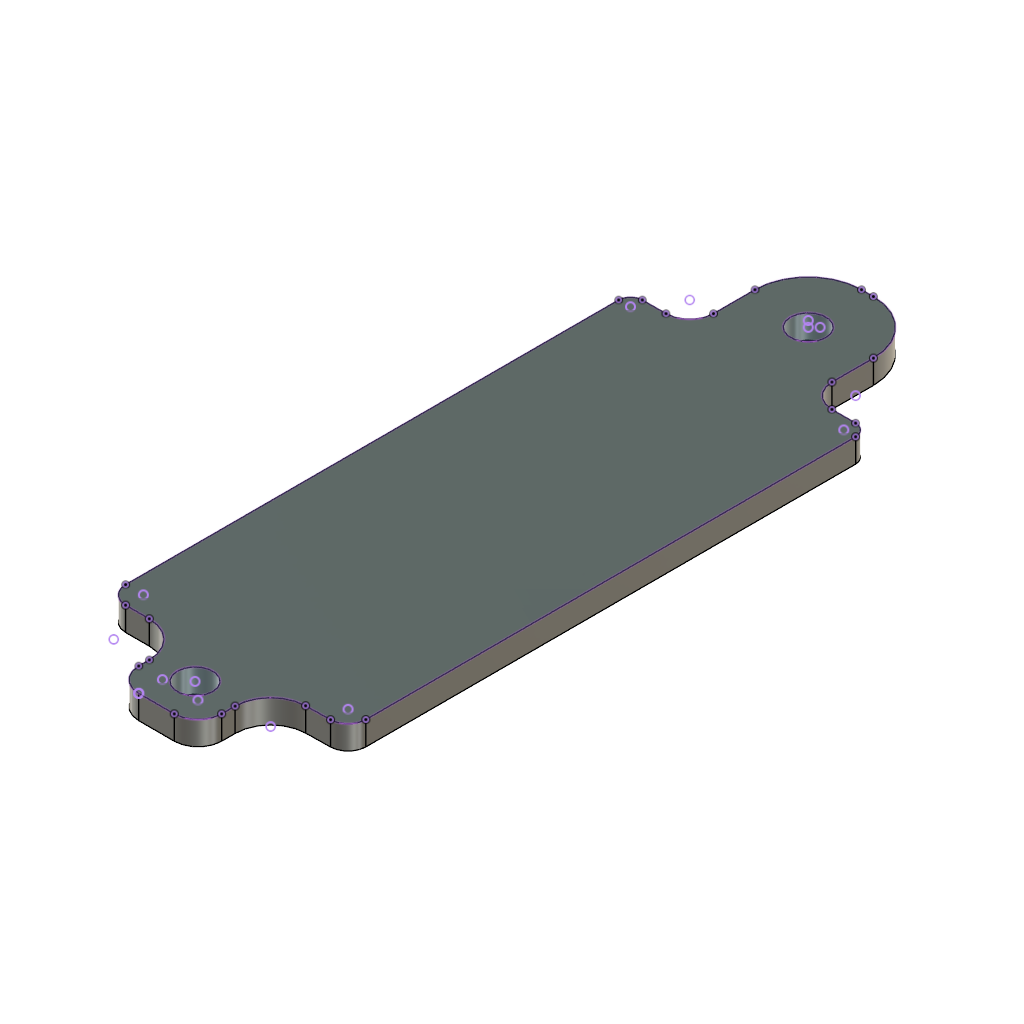
IM_glove_2 (Autodesk Fusion 360 archive; units mm, degrees)
design "fleje 20mm"
Autodesk Fusion 360 part; units mm, degrees
sketch "Boceto1" plane through (0, 0, 0) normal (0, 0, 1) x (1, 0, 0)
  line L0 (0, 0) -> (0, 45)
  line L1 (0, 45) -> (0, 55)
  line L2 (0, 55) -> (0, 50)
  circle A0 centre (0, 50) radius 1.5
  line L3 (0, 0) -> (0, -3.5)
  line L4 (0, -3.5) -> (0, -1.75)
  circle A1 centre (0, -1.75) radius 1.5
  line L5 (0, 0) -> (0, 17.5)
  line L6 (0, 17.5) -> (0, 45)
  line L7 (-7, 45) -> (-9, 45)
  line L8 (7, 45) -> (9, 45)
  line L9 (10, 44) -> (10, 2.6675)
  line L10 (-6.5, 0.8929) -> (-8.5, 0.8929)
  line L11 (-10, 2.3929) -> (-10, 44)
  line L12 (0, 0) -> (-3.5, 0)
  line L13 (0, 0) -> (3.5, 0)
  line L14 (-3.5, 0) -> (3.5, 0)
  line L15 (3.5, -1.8653) -> (3.5, -3)
  line L16 (1.5, -5) -> (-1.5, -5)
  line L17 (-3.5, -3) -> (-3.5, -2.1071)
  line L18 (0, 45) -> (-5, 45)
  line L19 (-5, 45) -> (5, 45)
  line L20 (5, 47) -> (5, 50.5)
  line L21 (0.5, 55) -> (-0.5, 55)
  line L22 (-5, 50.5) -> (-5, 47)
  arc A2 (10, 44) -> (9, 45) centre (9, 44) ccw
  arc A3 (5, 47) -> (7, 45) centre (7, 47) ccw
  arc A4 (-9, 45) -> (-10, 44) centre (-9, 44) ccw
  arc A5 (-7, 45) -> (-5, 47) centre (-7, 47) ccw
  arc A6 (-0.5, 55) -> (-5, 50.5) centre (-0.5, 50.5) ccw
  arc A7 (5, 50.5) -> (0.5, 55) centre (0.5, 50.5) ccw
  arc A8 (-10, 2.3929) -> (-8.5, 0.8929) centre (-8.5, 2.3929) ccw
  arc A9 (-3.5, -2.1071) -> (-6.5, 0.8929) centre (-6.5, -2.1071) ccw
  line L23 (6.4516, 1.1343) -> (8.5242, 1.1677)
  arc A10 (8.5242, 1.1677) -> (10, 2.6675) centre (8.5, 2.6675) ccw
  arc A11 (6.4516, 1.1343) -> (3.5, -1.8653) centre (6.5, -1.8653) ccw
  arc A12 (-3.5, -3) -> (-1.5, -5) centre (-1.5, -3) ccw
  arc A13 (1.5, -5) -> (3.5, -3) centre (1.5, -3) ccw
  point P0 (-10, 45)
  point P1 (10, 45)
  point P2 (-3.5, -5)
  point P3 (-5, 55)
  dimension "d1" = 45
  dimension "d2" = 10
  dimension "d3" = 3
  dimension "d4" = 3.5
  dimension "d5" = 3
  dimension "d6" = 17.5
  dimension "d7" = 10
  dimension "d8" = 20
  dimension "d9" = 3.5
  dimension "d10" = 3.5
  dimension "d11" = 7
  dimension "d12" = 5
  dimension "d13" = 5
  dimension "d14" = 10
  dimension "d15" = 10
  dimension "d16" = 1
  dimension "d17" = 2
  dimension "d18" = 1
  dimension "d19" = 2
  dimension "d20" = 4.5
  dimension "d21" = 4.5
  dimension "d22" = 1.5
  dimension "d23" = 3
  dimension "d24" = 1.5
  dimension "d25" = 3
  dimension "d26" = 2
  dimension "d27" = 2
  constraint coincident L0.start L3.start
  constraint vertical L0
  constraint parallel L0 L1
  constraint midpoint L1 L2.end
  constraint coincident L2.end A0.centre
  constraint parallel L0 L3
  constraint midpoint L3 L4.end
  constraint coincident L4.end A1.centre
  constraint parallel L0 L5
  constraint perpendicular L0 L7
  constraint horizontal L8
  constraint vertical L9
  constraint horizontal L10
  constraint vertical L11
  constraint perpendicular L3 L12
  constraint perpendicular L0 L13
  constraint horizontal L14
  constraint vertical L15
  constraint horizontal L16
  constraint vertical L17
  constraint coincident L8 L18.end
  constraint horizontal L19
  constraint vertical L20
  constraint horizontal L21
  constraint vertical L22
  constraint coincident P1 L9
  constraint coincident P1 L8
  constraint tangent L9 A2
  constraint tangent L8 A2
  constraint coincident L19.end L20
  constraint coincident P0 L8
  constraint tangent L20 A3
  constraint tangent L8 A3
  constraint coincident P0 L7
  constraint coincident P0 L11
  constraint tangent L7 A4
  constraint tangent L11 A4
  constraint coincident L18.end L22
  constraint coincident L0.end L7
  constraint tangent L22 A5
  constraint tangent L7 A5
  constraint coincident P3 L22
  constraint coincident P3 L21
  constraint tangent L22 A6
  constraint tangent L21 A6
  constraint tangent L20 A7
  constraint tangent L21 A7
  constraint tangent L10 A8
  constraint tangent L11 A8
  constraint coincident L12.end L17
  constraint tangent L10 A9
  constraint tangent L17 A9
  constraint tangent L9 A10
  constraint tangent L23 A10
  constraint coincident L10.end L23
  constraint coincident L13.end L15
  constraint tangent L23 A11
  constraint tangent L15 A11
  constraint coincident P2 L16
  constraint coincident P2 L17
  constraint tangent L16 A12
  constraint tangent L17 A12
  constraint tangent L15 A13
  constraint tangent L16 A13
  measures "d1" distance of L0.start L0.end
  measures "d2" distance of L0.end L1.end
  measures "d3" diameter of A0
  measures "d4" distance of L0.start L3.end
  measures "d5" diameter of A1
  measures "d6" distance of L0.start L5.end
  measures "d7" distance of L0.end P0
  measures "d8" distance of P0 P1
  measures "d9" distance of L0.start L12.end
  measures "d10" distance of L0.start L13.end
  measures "d11" distance of L12.end L13.end
  measures "d12" distance of L12.end P2
  measures "d13" distance of L0.end L18.end
  measures "d14" distance of L18.end L19.end
  measures "d15" distance of L18.end P3
  measures "d16" radius of A2
  measures "d17" radius of A3
  measures "d18" radius of A4
  measures "d19" radius of A5
  measures "d20" radius of A6
  measures "d21" radius of A7
  measures "d22" radius of A8
  measures "d23" radius of A9
  measures "d24" radius of A10
  measures "d25" radius of A11
  measures "d26" radius of A12
  measures "d27" radius of A13
extrude "Extruir1" add sketch "Boceto1" along normal blind 2
sketch "Boceto2" plane through (0, 0, 2) normal (0, 0, 1) x (-1, 0, 0)
  circle A0 centre (0, -50) radius 1.5
  arc A1 (3.5, 3) -> (1.5, 5) centre (1.5, 3) ccw
  arc A2 (-1.5, 5) -> (-3.5, 3) centre (-1.5, 3) ccw
  arc A3 (-6.4516, -1.1343) -> (-3.5, 1.8653) centre (-6.5, 1.8653) ccw
  line L0 (-6.4516, -1.1343) -> (-8.5242, -1.1677)
  arc A4 (-8.5242, -1.1677) -> (-10, -2.6675) centre (-8.5, -2.6675) ccw
  line L1 (-10, -2.6675) -> (-10, -44)
  arc A5 (-10, -44) -> (-9, -45) centre (-9, -44) ccw
  line L2 (-9, -45) -> (-7, -45)
  arc A6 (-5, -47) -> (-7, -45) centre (-7, -47) ccw
  line L3 (-5, -47) -> (-5, -50.5)
  arc A7 (-5, -50.5) -> (-0.5, -55) centre (-0.5, -50.5) ccw
  line L4 (-0.5, -55) -> (0.5, -55)
  arc A8 (0.5, -55) -> (5, -50.5) centre (0.5, -50.5) ccw
  line L5 (5, -50.5) -> (5, -47)
  arc A9 (7, -45) -> (5, -47) centre (7, -47) ccw
  line L6 (7, -45) -> (9, -45)
  arc A10 (9, -45) -> (10, -44) centre (9, -44) ccw
  line L7 (10, -44) -> (10, -2.3929)
  arc A11 (10, -2.3929) -> (8.5, -0.8929) centre (8.5, -2.3929) ccw
  line L8 (8.5, -0.8929) -> (6.5, -0.8929)
  arc A12 (3.5, 2.1071) -> (6.5, -0.8929) centre (6.5, 2.1071) ccw
  line L9 (3.5, 2.1071) -> (3.5, 3)
  line L10 (1.5, 5) -> (-1.5, 5)
  line L11 (-3.5, 3) -> (-3.5, 1.8653)
  circle A13 centre (0, 1.75) radius 1.5
equation "d4 = 10.500 mm - 7 mm"
equation "d6 = ( 35 / 2 ) * 1 mm"
equation "d7 = ( 20 / 2 ) * 1 mm"
equation "d12 = 10.5 mm - 5.5 mm"
